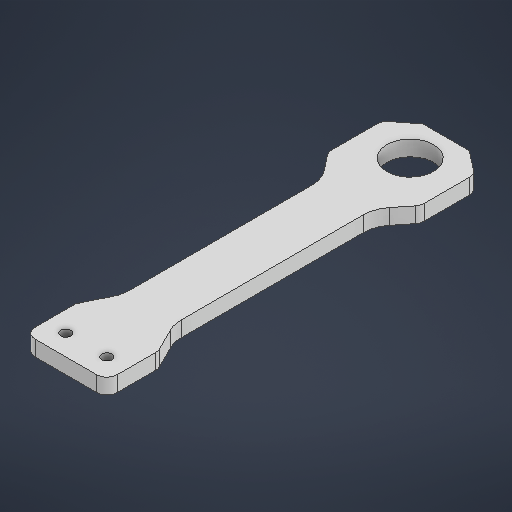
# Autodesk Inventor part: thanhlk 5
Saved by Autodesk Inventor 2027 (Build 310192060, 192F)
## iProperties
Created: 2026-08-21
Part Number: thanhlk 5
Material: Generic
Document SubType Name: Modeling
Designer: thita
Density: 1 g/cm^3
Appearance: Default
Author: thita
Autodesk Inventor part; units mm, degrees
ref_plane "YZ Plane" through (0, 0, 0) normal (1, 0, 0) x (0, 1, 0)
ref_plane "XZ Plane" through (0, 0, 0) normal (0, 1, 0) x (-1, 0, 0)
ref_plane "XY Plane" through (0, 0, 0) normal (0, 0, 1) x (1, 0, 0)
sketch "Sketch1" plane through (0, 0, 0) normal (0, 1, 0) x (-1, 0, 0)
  arc A0 (5, 14.1047) -> (6.3148, 10.3565) centre (11, 14.1047) ccw
  line L0 (5, 14.1047) -> (5, 49.5836)
  arc A1 (5.6334, 52.2669) -> (5, 49.5836) centre (11, 49.5836) ccw
  line L1 (5.6334, 52.2669) -> (7.7889, 56.5777)
  arc A2 (7.7889, 56.5777) -> (8, 57.4721) centre (6, 57.4721) ccw
  line L2 (8, 57.4721) -> (8, 65)
  arc A3 (8, 65) -> (6, 67) centre (6, 65) ccw
  line L3 (6, 67) -> (-6, 67)
  arc A4 (-6, 67) -> (-8, 65) centre (-6, 65) ccw
  line L4 (-8, 65) -> (-8, 57.4721)
  arc A5 (-8, 57.4721) -> (-7.7889, 56.5777) centre (-6, 57.4721) ccw
  line L5 (-7.7889, 56.5777) -> (-5.6334, 52.2669)
  arc A6 (-5, 49.5836) -> (-5.6334, 52.2669) centre (-11, 49.5836) ccw
  line L6 (-5, 49.5836) -> (-5, 14.1047)
  arc A7 (-6.3148, 10.3565) -> (-5, 14.1047) centre (-11, 14.1047) ccw
  line L7 (-6.3148, 10.3565) -> (-8.5617, 7.5478)
  arc A8 (-8.5617, 7.5478) -> (-9, 6.2984) centre (-7, 6.2984) ccw
  line L8 (-9, 6.2984) -> (-9, -2.5218)
  arc A9 (-9, -2.5218) -> (-8.2279, -4.1005) centre (-7, -2.5218) ccw
  line L9 (-8.2279, -4.1005) -> (-4.5, -7)
  line L10 (-4.5, -7) -> (4.5, -7)
  line L11 (4.5, -7) -> (8.2279, -4.1005)
  arc A10 (8.2279, -4.1005) -> (9, -2.5218) centre (7, -2.5218) ccw
  line L12 (9, -2.5218) -> (9, 6.2984)
  arc A11 (9, 6.2984) -> (8.5617, 7.5478) centre (7, 6.2984) ccw
  line L13 (8.5617, 7.5478) -> (6.3148, 10.3565)
  circle A12 centre (-4, 63) radius 1
  circle A13 centre (4, 63) radius 1
  arc A14 (3, 2.6458) -> (-3, 2.6458) centre (0, 0) ccw
  arc A15 (-3, -2.6458) -> (3, -2.6458) centre (0, 0) ccw
  circle A16 centre (0, 0) radius 4.55
  dimension "d0" = 9.1
  constraints: 28 end point, 28 point on circle, 17 centre point, 1 coincident
  measures "d0" diameter of A16
extrude "Extrusion1" add sketch "Sketch1" along normal blind 3
body "Solid1"
